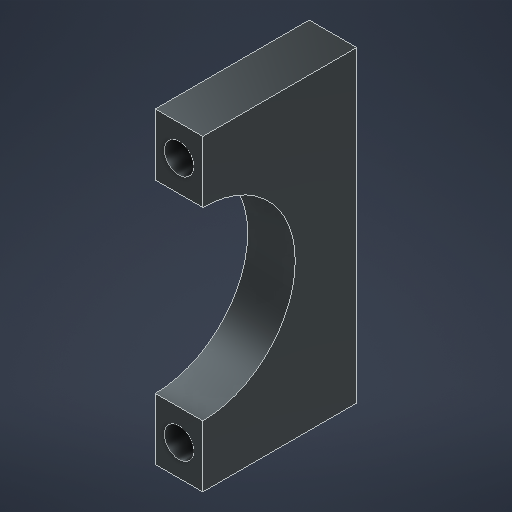
# Autodesk Inventor part: V6_Main_Bearing_Cap
Saved by Autodesk Inventor 2027.1 (Build 311270010, 270A)
## iProperties
Created: 2026-10-17
Part Number: V6_Main_Bearing_Cap
Material: Iron, Ductile
Document SubType Name: Modeling
Designer: kashyap
Density: 7.15 g/cm^3
Appearance: Iron Gray
Mass: 459.162 g
Surface Area: 182.086 cm^2
Volume: 64.2185 cm^3
Material_Status: Assumed for this reconstruction
Author: kashyap
Autodesk Inventor part; units mm, degrees
ref_plane "YZ Plane" through (0, 0, 0) normal (1, 0, 0) x (0, 1, 0)
ref_plane "XZ Plane" through (0, 0, 0) normal (0, 1, 0) x (-1, 0, 0)
ref_plane "XY Plane" through (0, 0, 0) normal (0, 0, 1) x (1, 0, 0)
derived "V6_Engine_Master.ipt"
sketch "SK_Main_Cap_Profile" plane through (0, 0, 0) normal (1, 0, 0) x (0, 1, 0)
  line L0 (-77, 0) -> (77, 0) construction
  line L1 (-55, 0) -> (-33.015, 0)
  line L2 (33.015, 0) -> (55, 0)
  line L3 (55, 0) -> (55, -55)
  line L4 (55, -55) -> (-55, -55)
  line L5 (-55, -55) -> (-55, 0)
  arc A0 (-33.015, 0) -> (33.015, 0) centre (0, 0) ccw
  dimension "d19" = 33.015
  dimension "d20" = 55
  dimension "d21" = 55
  dimension "d22" = 55
  constraints: 10 end point, 2 collinear, 2 point on circle, 2 vertical, 1 centre point, 1 coincident, 1 horizontal
  measures "d19" radius of A0
  measures "d20" distance of point (0, 0) L2.end
  measures "d21" distance of point (0, 0) L1.start
  measures "d22" distance between parallel lines of L4 L0
extrude "Main_Cap_Body" add sketch "SK_Main_Cap_Profile" along normal mid plane 17
sketch "SK_Main_Cap_Bolt_Holes" plane through (0, 0, 0) normal (0, 0, 1) x (1, 0, 0)
  point P0 (0, 0)
  point P1 (0, 44)
  point P2 (0, -44)
  dimension "d25" = 44
  dimension "d26" = 0
  dimension "d27" = 44
  dimension "d28" = 0
  measures "d25" distance of point (0, 0) point (0, 44)
  measures "d26" horizontal distance of point (0, 0) point (0, 44)
  measures "d27" distance of point (0, 0) point (0, -44)
  measures "d28" horizontal distance of point (0, 0) point (0, -44)
hole "Main_Cap_Bolt_Holes" at (0, 44, 0) at (0, -44, 0) direction (0, 0, -1) diameter 10.5 depth 55
equation "\"d19\" = 0.5 * Main_Housing_Bore"
equation "\"d20\" = Main_Cap_Half_Width"
equation "\"d21\" = Main_Cap_Half_Width"
equation "\"d22\" = Main_Cap_Depth"
equation "\"d23\" = Main_Web_Thickness"
equation "\"d25\" = Main_Cap_Bolt_Y"
equation "\"d27\" = Main_Cap_Bolt_Y"
equation "\"d36\" = Main_Cap_Bolt_Clear_Dia"
equation "\"d41\" = Main_Cap_Depth"
equation "\"Main_Housing_Bore\" = 66.03"
equation "\"Main_Cap_Depth\" = 55"
equation "\"Main_Web_Thickness\" = 17"
equation "\"Main_Cap_Bolt_Clear_Dia\" = 10.5"
equation "\"Main_Cap_Half_Width\" = 55"
equation "\"Main_Cap_Bolt_Y\" = 44"
body "Solid1"
